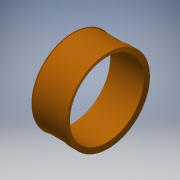
# Autodesk Inventor part: 15-0012-0306
Saved by Autodesk Inventor 2016 SP2 (Build 200236200, 236)
## iProperties
Created: 2017-10-23
Part Number: 15-0012-0306
Material: Plastic (PEEK)
Document SubType Name: Modeling
Designer: jellerm1
Density: 1.32 g/cm^3
Appearance: Orange
Project: Quantum Gas Microscope
Cost Center: 15-0012
User Status: Work in Progress
Authority: Georgios Siviloglou
RuleStatus: InUse
Category: IOP
Company: Universiteit van Amsterdam
BeforeDocSave0: Open Form
Author: jellerm1
Title: Quantum Gas Microscope
Revision Number: A
Autodesk Inventor part; units mm, degrees
ref_plane "YZ Plane" through (0, 0, 0) normal (1, 0, 0) x (0, 1, 0)
ref_plane "XZ Plane" through (0, 0, 0) normal (0, 1, 0) x (-1, 0, 0)
ref_plane "XY Plane" through (0, 0, 0) normal (0, 0, 1) x (1, 0, 0)
sketch "Sketch1" plane through (0, 0, 0) normal (0, 0, 1) x (1, 0, 0)
  line L0 (0, 125.258) -> (0, -125.258) construction
  line L1 (-46.17, 0) -> (242.44, 0) construction
  line L2 (0, 22.5) -> (25.1323, 22.5)
  line L3 (25.1323, 22.5) -> (25.938, 25.4)
  line L4 (25.938, 25.4) -> (-0.2537, 25.4)
  line L5 (-0.2537, 25.4) -> (0, 22.5) construction
  line L6 (0, 0) -> (27.5804, 0)
  circle A0 centre (111.74, 0) radius 89.47 construction
  line L7 (13.8603, 23.95) -> (25.5351, 23.95) construction
  circle A1 centre (33.65, 0) radius 38.59 construction
  line L8 (4.6293, 23.95) -> (3.3914, 23.95) construction
  arc A2 (5.2638, 25.4) -> (5.2638, 22.5) centre (5.2638, 23.95) ccw
  line L9 (5.2638, 23.95) -> (4.1555, 24.885) construction
  line L10 (11.2638, 26.9) -> (19.2638, 26.9)
  line L11 (19.2638, 26.9) -> (19.2638, 24.9)
  line L12 (19.2638, 24.9) -> (11.2638, 24.9)
  line L13 (11.2638, 24.9) -> (11.2638, 26.9)
  line L14 (12.8421, 26.9) -> (12.8421, 71.7537) construction
  line L15 (12.8421, 25.4) -> (12.8421, 19.6495) construction
  dimension "d4" = 178.94
  dimension "d0" = 50.8
  dimension "d1" = 45
  dimension "d2" = 95
  dimension "d3" = 0
  dimension "d5" = 111.74
  dimension "d6" = 1.45
  dimension "d8" = 77.18
  dimension "d9" = 78.09
  dimension "d10" = 1.45
  dimension "d11" = 2
  dimension "d12" = 8
  dimension "d13" = 0.5
  dimension "d14" = 6.6742
  dimension "d17" = 6
  constraints: 28 end point, 6 point on line, 5 point on circle, 3 horizontal, 3 parallel, 3 perpendicular, 2 centre point, 2 midpoint, 2 tangent, 1 collinear, 4 other
  measures "d0" diameter of L4 L6
  measures "d1" diameter of L2 L6
  measures "d2" angle of L2 L5
  measures "d3" distance from line of L0 L2.start
  measures "d5" distance from line of point (111.74, 0) L0
  measures "d6" distance between parallel lines of L7 L2
  measures "d8" diameter of A1
  measures "d9" distance of point (111.74, 0) A1.centre
  measures "d10" distance between parallel lines of L4 L8
  measures "d11" distance of L12.end L10.start
  measures "d12" distance of L10.start L10.end
  measures "d13" distance between parallel lines of L4 L12
  measures "d14" distance from line of L3.end L11
  measures "d17" distance from line of A2.start L13
revolve "Revolution1" add sketch "Sketch1" angle 360 about axis through (0, 0, 0) along (1, 0, 0) contours A2 L4 L13 L12 L11 L3 L2 | L4 L11 L12 L13
revolve "Revolution2" cut sketch "Sketch1" angle 360 about axis through (0, 0, 0) along (1, 0, 0) contours L13 L10 L11 L4 | L4 L11 L12 L13
equation "\"d10\" = -0.25 * d1 + 0.25 * d0"
body "Solid1"
